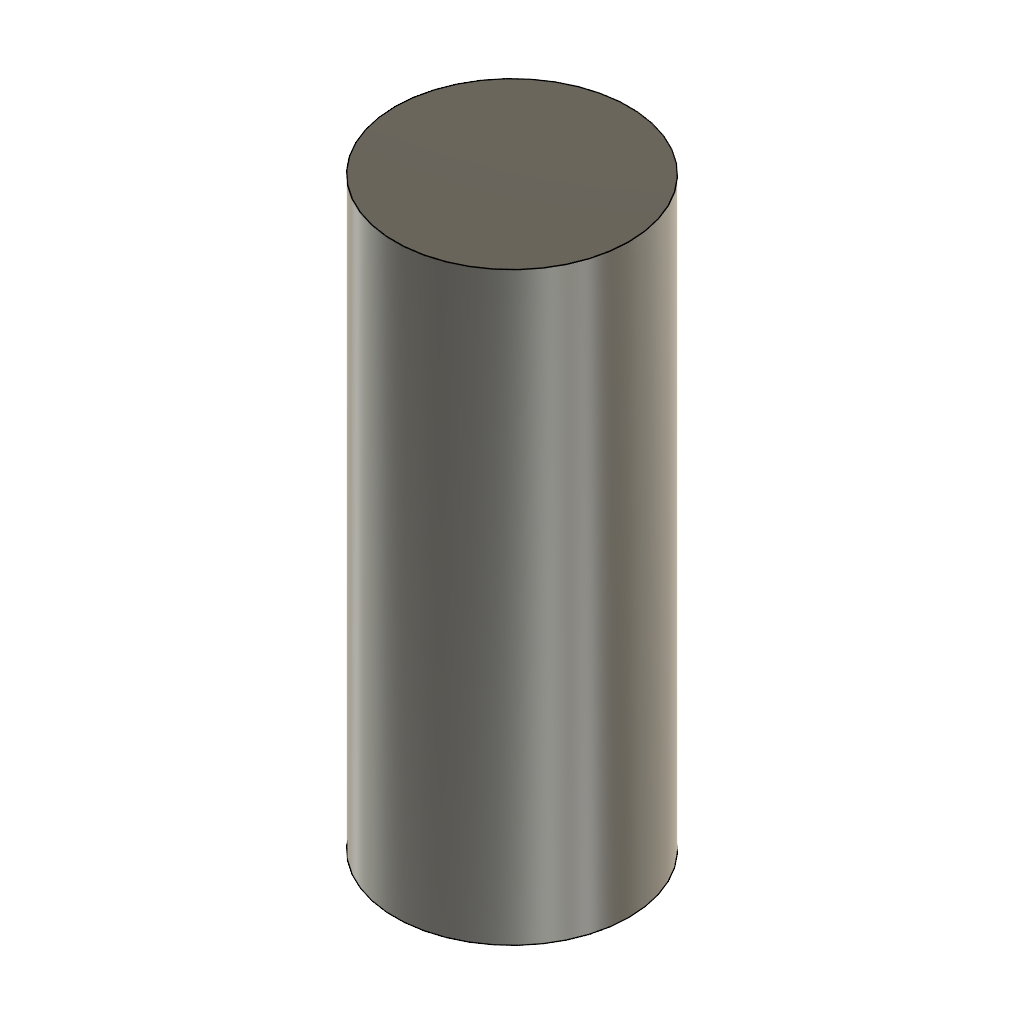
BG_Topfkern (Autodesk Fusion 360 archive; units mm, degrees)
design "Mittelpol"
part number: 2026-10-08-12-51-46-358
Autodesk Fusion 360 part; units mm, degrees
sketch "Skizze1" plane through (0, 0, 0) normal (0, 0, 1) x (1, 0, 0)
  circle A0 centre (0, 0) radius 20
  dimension "d1" = 40
  constraint coincident A0.centre origin
  measures "d1" diameter of A0
extrude "Extrusion1" add sketch "Skizze1" along normal blind 100

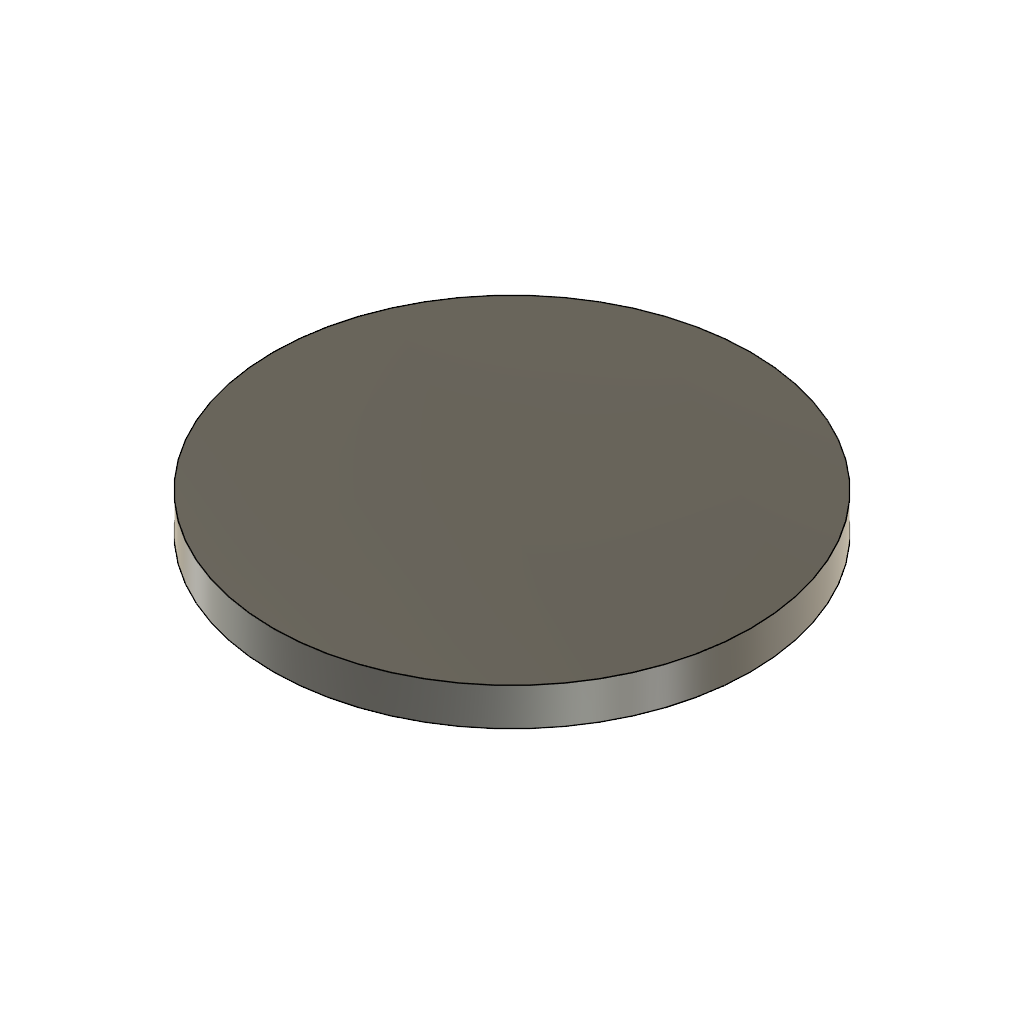
design "Rückwand"
part number: 2026-10-08-12-39-34-155
Autodesk Fusion 360 part; units mm, degrees
sketch "Skizze1" plane through (0, 0, 0) normal (0, 0, 1) x (1, 0, 0)
  circle A0 centre (0, 0) radius 63.5
  dimension "d3" = 127
  constraint coincident A0.centre origin
  measures "d3" diameter of A0
extrude "Extrusion1" add sketch "Skizze1" along normal blind 10

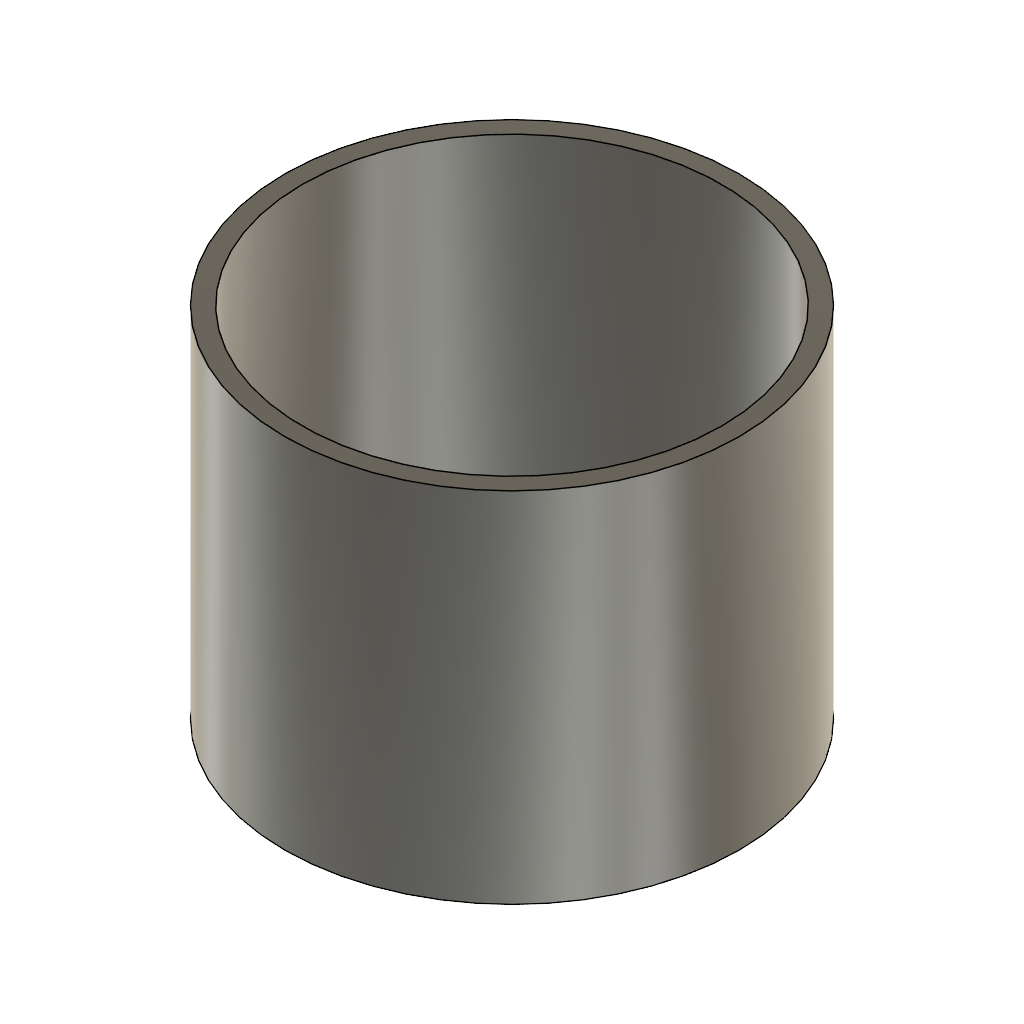
design "Aussenmantel"
part number: 2026-10-08-12-49-27-427
Autodesk Fusion 360 part; units mm, degrees
sketch "Skizze1" plane through (0, 0, 0) normal (0, 0, 1) x (1, 0, 0)
  circle A0 centre (0, 0) radius 63.5
  circle A1 centre (0, 0) radius 58.5
  dimension "d1" = 117
  dimension "d2" = 127
  constraint coincident A0.centre A1.centre
  measures "d1" diameter of A1
  measures "d2" diameter of A0
extrude "Extrusion1" add sketch "Skizze1" along normal blind 100
